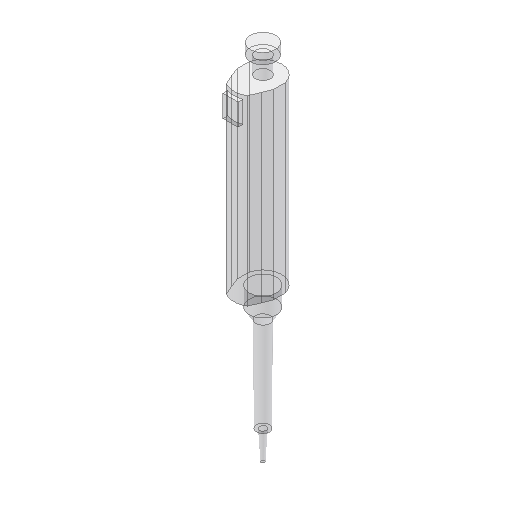
# Autodesk Inventor part: REF - OT2-Pipette V0.3 - ONiLAB envelope
Saved by Autodesk Inventor 2025.5 (Build 295498000, 498)
## iProperties
Created: 2026-11-01
Part Number: REF - OT2-Pipette V0.3 - ONiLAB envelope
Material: Generisch
Description: ONiLAB 0.1-2.5 ul envelope: Dev-Core body (hook cut), photo lower part, ejector button
Document SubType Name: Modeling
Designer: benir
Density: 1 g/cm^3
Appearance: Clear
Author: benir
Autodesk Inventor part; units mm, degrees
ref_plane "y=body_bottom" through (0, -66, 0) normal (0, 1, 0) x (-1, 0, 0)
sketch "body" plane through (0, -66, 0) normal (0, 1, 0) x (-1, 0, 0)
  arc A0 (-20.2, -6.2935) -> (3.8, -6.2935) centre (-8.2, -3.46) ccw
  arc A1 (-1.2, 13.79) -> (-15.2, 13.79) centre (-8.2, 2.54) ccw
  line L0 (3.8, -6.2935) -> (3.8, 1.71)
  line L1 (3.8, 1.71) -> (1.58, 7.29)
  line L2 (1.58, 7.29) -> (-1.2, 13.79)
  line L3 (-15.2, 13.79) -> (-17.98, 7.29)
  line L4 (-17.98, 7.29) -> (-20.2, 1.71)
  line L5 (-20.2, 1.71) -> (-20.2, -6.2935)
  point P0 (0, 0)
  dimension "d3" = 3.46
  dimension "d4" = 8.2
  dimension "d5" = 2.54
  dimension "d6" = 8.2
  dimension "d7" = 6.2935
  dimension "d8" = 20.2
  dimension "d9" = 3.8
  dimension "d10" = 13.79
  dimension "d11" = 15.2
  dimension "d12" = 1.2
  dimension "d13" = 1.71
  dimension "d14" = 3.8
  dimension "d15" = 7.29
  dimension "d16" = 1.58
  dimension "d17" = 7.29
  dimension "d18" = 17.98
  dimension "d19" = 1.71
  dimension "d20" = 20.2
  constraints: 12 end point, 4 point on circle, 2 centre point
  measures "d3" vertical distance of point (0, 0) A0.centre
  measures "d4" horizontal distance of point (0, 0) A0.centre
  measures "d5" vertical distance of point (0, 0) A1.centre
  measures "d6" horizontal distance of point (0, 0) A1.centre
  measures "d7" vertical distance of point (0, 0) L5.end
  measures "d8" horizontal distance of point (0, 0) L5.end
  measures "d9" horizontal distance of point (0, 0) L0.start
  measures "d10" vertical distance of point (0, 0) L3.start
  measures "d11" horizontal distance of point (0, 0) L3.start
  measures "d12" horizontal distance of point (0, 0) L2.end
  measures "d13" vertical distance of point (0, 0) L0.end
  measures "d14" horizontal distance of point (0, 0) L0.end
  measures "d15" vertical distance of point (0, 0) L1.end
  measures "d16" horizontal distance of point (0, 0) L1.end
  measures "d17" vertical distance of point (0, 0) L3.end
  measures "d18" horizontal distance of point (0, 0) L3.end
  measures "d19" vertical distance of point (0, 0) L4.end
  measures "d20" horizontal distance of point (0, 0) L4.end
extrude "body (hook cut off)" add sketch "body" along normal blind 121
ref_plane "y=body_top" through (0, 55, 0) normal (0, 1, 0) x (-1, 0, 0)
sketch "plunger stem" plane through (0, 55, 0) normal (0, 1, 0) x (-1, 0, 0)
  circle A0 centre (-8.2, -3.46) radius 4.95
  point P0 (0, 0)
  dimension "d24" = 3.46
  dimension "d25" = 8.2
  dimension "d26" = 9.9
  constraints: 1 centre point
  measures "d24" vertical distance of point (0, 0) A0.centre
  measures "d25" horizontal distance of point (0, 0) A0.centre
  measures "d26" diameter of A0
extrude "Extrusion3" add sketch "plunger stem" along normal blind 11.5
ref_plane "y=knob_y0" through (0, 66.5, 0) normal (0, 1, 0) x (-1, 0, 0)
sketch "knob" plane through (0, 66.5, 0) normal (0, 1, 0) x (-1, 0, 0)
  circle A0 centre (-8.2, -3.46) radius 8.3
  point P0 (0, 0)
  dimension "d30" = 3.46
  dimension "d31" = 8.2
  dimension "d32" = 16.6
  constraints: 1 centre point
  measures "d30" vertical distance of point (0, 0) A0.centre
  measures "d31" horizontal distance of point (0, 0) A0.centre
  measures "d32" diameter of A0
extrude "plunger knob" add sketch "knob" along normal blind 7
ref_plane "z=pip_z" through (0, 0, -3.46) normal (0, 0, 1) x (1, 0, 0)
sketch "lower part section" plane through (0, 0, -3.46) normal (0, 0, 1) x (1, 0, 0)
  line L0 (8.2, -167.5) -> (9.4, -167.5)
  line L1 (9.4, -167.5) -> (10.55, -148.4)
  line L2 (10.55, -148.4) -> (12.5, -148.4)
  line L3 (12.5, -148.4) -> (12.9, -85.8)
  line L4 (12.9, -85.8) -> (17.25, -78.6)
  line L5 (17.25, -78.6) -> (17.25, -66)
  line L6 (17.25, -66) -> (8.2, -66)
  line L7 (8.2, -66) -> (8.2, -167.5)
  line L8 (8.2, 121.7) -> (8.2, -215.7) projected
  point P0 (0, 0)
  dimension "d36" = 167.5
  dimension "d37" = 8.2
  dimension "d38" = 167.5
  dimension "d39" = 9.4
  dimension "d40" = 148.4
  dimension "d41" = 10.55
  dimension "d42" = 148.4
  dimension "d43" = 12.5
  dimension "d44" = 85.8
  dimension "d45" = 12.9
  dimension "d46" = 78.6
  dimension "d47" = 17.25
  dimension "d48" = 66
  dimension "d49" = 17.25
  dimension "d50" = 66
  dimension "d51" = 8.2
  constraints: 16 end point
  measures "d36" vertical distance of point (0, 0) L0.start
  measures "d37" horizontal distance of point (0, 0) L0.start
  measures "d38" vertical distance of point (0, 0) L0.end
  measures "d39" horizontal distance of point (0, 0) L0.end
  measures "d40" vertical distance of point (0, 0) L1.end
  measures "d41" horizontal distance of point (0, 0) L1.end
  measures "d42" vertical distance of point (0, 0) L2.end
  measures "d43" horizontal distance of point (0, 0) L2.end
  measures "d44" vertical distance of point (0, 0) L3.end
  measures "d45" horizontal distance of point (0, 0) L3.end
  measures "d46" vertical distance of point (0, 0) L4.end
  measures "d47" horizontal distance of point (0, 0) L4.end
  measures "d48" vertical distance of point (0, 0) L5.end
  measures "d49" horizontal distance of point (0, 0) L5.end
  measures "d50" vertical distance of point (0, 0) L6.end
  measures "d51" horizontal distance of point (0, 0) L6.end
ref_plane "x=pip_x" through (8.2, 0, 0) normal (1, 0, 0) x (0, 1, 0)
revolve "collar, ejector sleeve, tip cone" add sketch "lower part section" angle 360 about axis through (8.2, 0, -3.46) along (0, -1, 0)
ref_plane "y=ej_top - ej_h" through (0, 38, 0) normal (0, 1, 0) x (-1, 0, 0)
sketch "ejector button" plane through (0, 38, 0) normal (0, 1, 0) x (-1, 0, 0)
  line L0 (-3.2, 8.84) -> (-13.2, 8.84)
  line L1 (-13.2, 8.84) -> (-13.2, 18.04)
  line L2 (-13.2, 18.04) -> (-3.2, 18.04)
  line L3 (-3.2, 18.04) -> (-3.2, 8.84)
  line L4 (0, -22.556) -> (0, 24.806) projected
  line L5 (8.6, 0) -> (-25, 0) projected
  point P0 (0, 0)
  dimension "d55" = 10
  dimension "d56" = 9.2
  dimension "d57" = 3.2
  dimension "d58" = 8.84
  constraints: 8 end point, 2 parallel, 1 horizontal, 1 perpendicular
  measures "d55" distance of L0.start L0.end
  measures "d56" distance of L2.end L0.start
  measures "d57" horizontal distance of point (0, 0) L2.end
  measures "d58" vertical distance of point (0, 0) L0.start
extrude "Extrusion5" add sketch "ejector button" along normal blind 14.5
equation "\"d3\" = -pip_z"
equation "\"d4\" = pip_x"
equation "\"d5\" = pip_z + nose_c"
equation "\"d6\" = pip_x"
equation "\"d8\" = pip_x + body_hw"
equation "\"d9\" = body_hw - pip_x"
equation "\"d11\" = pip_x + nose_hw"
equation "\"d12\" = pip_x - nose_hw"
equation "\"d13\" = pip_z + body_flat_d"
equation "\"d14\" = body_hw - pip_x"
equation "\"d15\" = pip_z + body_ch_d"
equation "\"d16\" = body_ch_w - pip_x"
equation "\"d17\" = pip_z + body_ch_d"
equation "\"d18\" = pip_x + body_ch_w"
equation "\"d19\" = pip_z + body_flat_d"
equation "\"d20\" = pip_x + body_hw"
equation "\"d21\" = body_len"
equation "\"d24\" = -pip_z"
equation "\"d25\" = pip_x"
equation "\"d26\" = plunger_d"
equation "\"d27\" = knob_y0 - body_top"
equation "\"d30\" = -pip_z"
equation "\"d31\" = pip_x"
equation "\"d32\" = knob_d"
equation "\"d33\" = knob_h"
equation "\"d36\" = -cone_end"
equation "\"d37\" = pip_x"
equation "\"d38\" = -cone_end"
equation "\"d39\" = pip_x + 0.5 * cone_d1"
equation "\"d40\" = -cone_len - cone_end"
equation "\"d41\" = pip_x + 0.5 * cone_d0"
equation "\"d42\" = -cone_len - cone_end"
equation "\"d43\" = pip_x + 0.5 * sleeve_d1"
equation "\"d44\" = -sleeve_len - cone_end - cone_len"
equation "\"d45\" = pip_x + 0.5 * sleeve_d0"
equation "\"d46\" = collar_len - body_bottom"
equation "\"d47\" = pip_x + 0.5 * collar_d"
equation "\"d48\" = -body_bottom"
equation "\"d49\" = pip_x + 0.5 * collar_d"
equation "\"d50\" = -body_bottom"
equation "\"d51\" = pip_x"
equation "\"d55\" = 2 * ej_hw + 0 * pip_x"
equation "\"d56\" = ej_d1 + 0 * pip_z - ej_d0"
equation "\"d57\" = pip_x - ej_hw"
equation "\"d58\" = pip_z + ej_d0"
equation "\"d59\" = ej_h"
equation "\"body_len\" = 121"
equation "\"plunger_d\" = 9.9"
equation "\"knob_y0\" = 66.5"
equation "\"body_top\" = 55"
equation "\"knob_d\" = 16.6"
equation "\"knob_h\" = 7"
equation "\"ej_hw\" = 5"
equation "\"pip_x\" = 8.2"
equation "\"ej_d1\" = 21.5"
equation "\"pip_z\" = -3.46"
equation "\"ej_d0\" = 12.3"
equation "\"ej_h\" = 14.5"
equation "\"nose_c\" = 6"
equation "\"body_hw\" = 12"
equation "\"nose_hw\" = 7"
equation "\"body_flat_d\" = 5.17"
equation "\"body_ch_d\" = 10.75"
equation "\"body_ch_w\" = 9.78"
equation "\"cone_end\" = -167.5"
equation "\"cone_d1\" = 2.4"
equation "\"cone_len\" = 19.1"
equation "\"cone_d0\" = 4.7"
equation "\"sleeve_d1\" = 8.6"
equation "\"sleeve_len\" = 62.6"
equation "\"sleeve_d0\" = 9.4"
equation "\"collar_len\" = 12.6"
equation "\"body_bottom\" = -66"
equation "\"collar_d\" = 18.1"
body "Solid2"
